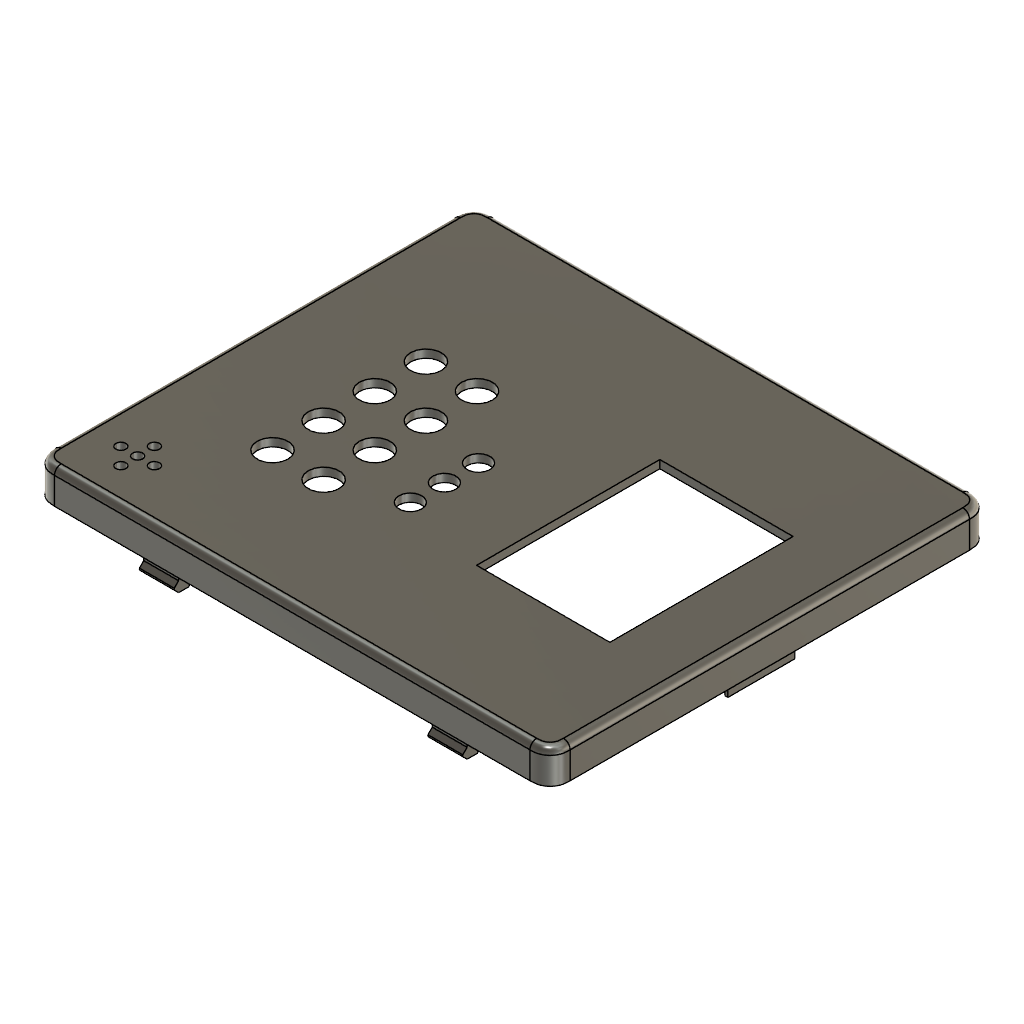
Крышка_пульта_клипсы_1.6_без_стоек (Autodesk Fusion 360 design; units mm, degrees)
part number: 2026-10-16-10-37-09-127
Autodesk Fusion 360 part; units mm, degrees
(part 1 of 3)
sketch "Sketch1" plane through (0, 0, 0) normal (0, 0, 1) x (1, 0, 0)
  line L0 (-25, 25) -> (41.8682, 25)
  line L1 (41.8682, 25) -> (41.8682, -32)
  line L2 (41.8682, -32) -> (-25, -32)
  line L3 (-25, -32) -> (-25, 25)
  dimension "d1" = 57
  constraint horizontal L0
  constraint vertical L1
  constraint horizontal L2
  constraint vertical L3
  measures "d1" distance of L0.start L2.end
extrude "Extrude1" add sketch "Sketch1" along normal blind 35 makes body 1
scale "Scale1" factor 1 about (-25, 25, 0) bodies 1
scale "Scale2" factor 1.105263 about (-25, 25, 35) bodies 1
scale "Scale3" factor 1.04 about (-25, -38, 35) bodies 1
fillet "Fillet1" radius 3 curvature continuous 4 edges at (-25, 27.52, 14.8842) (-25, -38, 14.8842) (51.8632, 27.52, 14.8842) (51.8632, -38, 14.8842) on bodies 1
ref_plane "WorkPlane1" through (13.4316, -5.24, 30) normal (0, 0, 1) x (1, 0, 0)
split "Split1" by plane through (13.4316, -5.24, 30) normal (0, 0, 1) bodies 1 makes body 2 at (1.6211, 5.68, 35)
move_body "Move1" bodies 2 to x (1, 0, 0) y (0, 1, 0) z (0, 0, 1) at (0, 0, 10)
extrude "Height clearance for 40 mm electronics" add 1 faces at (1.6211, 5.68, 30) along direction (0, 0, 1) blind 4 on bodies 1 bodies 1
shell "PETG housing walls 1.6 mm" thickness 1.2 removed faces 1 at (1.6211, 5.68, 34) on bodies 1
move_body "Assembled lid at housing rim" bodies 2 to x (1, 0, 0) y (0, 1, 0) z (0, 0, 1) at (0, 0, -6)
shell "PETG lid skin 1.2 mm" thickness 1.2 removed faces 1 at (1.6211, 5.68, 34) on bodies 2
ref_plane "WorkPlane2" through (0, 0, 30.2) normal (0, 0, 1) x (1, 0, 0)
sketch "PETG flexible clip -1 0" plane through (0, 0, 30.2) normal (0, 0, 1) x (1, 0, 0)
  line L0 (-10.6, -36.1) -> (-5.4, -36.1)
  line L1 (-5.4, -36.1) -> (-5.4, -35.3)
  line L2 (-5.4, -35.3) -> (-10.6, -35.3)
  line L3 (-10.6, -35.3) -> (-10.6, -36.1)
extrude "PETG flexible clip -1 0 (1)" add sketch "PETG flexible clip -1 0" along normal blind 7.8 bodies 2
ref_plane "WorkPlane3" through (-10.6, 0, 0) normal (1, 0, 0) x (0, 1, 0)
sketch "Latch ramp -1 0" plane through (-10.6, 0, 0) normal (1, 0, 0) x (0, 0, -1)
  line L0 (-30.2, -36.1) -> (-30.85, -36.75)
  line L1 (-30.85, -36.75) -> (-31.1, -36.75)
  line L2 (-31.1, -36.75) -> (-31.75, -36.1)
  line L3 (-31.75, -36.1) -> (-30.2, -36.1)
extrude "Latch ramp -1 0 (1)" add sketch "Latch ramp -1 0" along normal blind 5.2 bodies 2
ref_plane "WorkPlane4" through (0, -38.1, 0) normal (0, 1, 0) x (0, 0, 1)
sketch "Release slot -1 0" plane through (0, -38.1, 0) normal (0, 1, 0) x (1, 0, 0)
  line L0 (-11, -30.6) -> (-5, -30.6)
  line L1 (-5, -30.6) -> (-5, -31.4)
  line L2 (-5, -31.4) -> (-11, -31.4)
  line L3 (-11, -31.4) -> (-11, -30.6)
extrude "Release slot -1 0 (1)" cut sketch "Release slot -1 0" along normal blind 2 bodies 1
ref_plane "WorkPlane5" through (0, 0, 30.2) normal (0, 0, 1) x (1, 0, 0)
sketch "PETG flexible clip -1 1" plane through (0, 0, 30.2) normal (0, 0, 1) x (1, 0, 0)
  line L0 (32.4, -36.1) -> (37.6, -36.1)
  line L1 (37.6, -36.1) -> (37.6, -35.3)
  line L2 (37.6, -35.3) -> (32.4, -35.3)
  line L3 (32.4, -35.3) -> (32.4, -36.1)
extrude "PETG flexible clip -1 1 (1)" add sketch "PETG flexible clip -1 1" along normal blind 7.8 bodies 2
ref_plane "WorkPlane6" through (32.4, 0, 0) normal (1, 0, 0) x (0, 1, 0)
sketch "Latch ramp -1 1" plane through (32.4, 0, 0) normal (1, 0, 0) x (0, 0, -1)
  line L0 (-30.2, -36.1) -> (-30.85, -36.75)
  line L1 (-30.85, -36.75) -> (-31.1, -36.75)
  line L2 (-31.1, -36.75) -> (-31.75, -36.1)
  line L3 (-31.75, -36.1) -> (-30.2, -36.1)
extrude "Latch ramp -1 1 (1)" add sketch "Latch ramp -1 1" along normal blind 5.2 bodies 2
ref_plane "WorkPlane7" through (0, -38.1, 0) normal (0, 1, 0) x (0, 0, 1)
sketch "Release slot -1 1" plane through (0, -38.1, 0) normal (0, 1, 0) x (1, 0, 0)
  line L0 (32, -30.6) -> (38, -30.6)
  line L1 (38, -30.6) -> (38, -31.4)
  line L2 (38, -31.4) -> (32, -31.4)
  line L3 (32, -31.4) -> (32, -30.6)
extrude "Release slot -1 1 (1)" cut sketch "Release slot -1 1" along normal blind 2 bodies 1
ref_plane "WorkPlane8" through (0, 0, 30.2) normal (0, 0, 1) x (1, 0, 0)
sketch "PETG flexible clip 1 0" plane through (0, 0, 30.2) normal (0, 0, 1) x (1, 0, 0)
  line L0 (-10.6, 24.82) -> (-5.4, 24.82)
  line L1 (-5.4, 24.82) -> (-5.4, 25.62)
  line L2 (-5.4, 25.62) -> (-10.6, 25.62)
  line L3 (-10.6, 25.62) -> (-10.6, 24.82)
extrude "PETG flexible clip 1 0 (1)" add sketch "PETG flexible clip 1 0" along normal blind 7.8 bodies 2
ref_plane "WorkPlane9" through (-10.6, 0, 0) normal (1, 0, 0) x (0, 1, 0)
sketch "Latch ramp 1 0" plane through (-10.6, 0, 0) normal (1, 0, 0) x (0, 0, -1)
  line L0 (-30.2, 25.62) -> (-30.85, 26.27)
  line L1 (-30.85, 26.27) -> (-31.1, 26.27)
  line L2 (-31.1, 26.27) -> (-31.75, 25.62)
  line L3 (-31.75, 25.62) -> (-30.2, 25.62)
extrude "Latch ramp 1 0 (1)" add sketch "Latch ramp 1 0" along normal blind 5.2 bodies 2
ref_plane "WorkPlane10" through (0, 27.62, 0) normal (0, 1, 0) x (0, 0, 1)
sketch "Release slot 1 0" plane through (0, 27.62, 0) normal (0, 1, 0) x (1, 0, 0)
  line L0 (-11, -30.6) -> (-5, -30.6)
  line L1 (-5, -30.6) -> (-5, -31.4)
  line L2 (-5, -31.4) -> (-11, -31.4)
  line L3 (-11, -31.4) -> (-11, -30.6)
extrude "Release slot 1 0 (1)" cut sketch "Release slot 1 0" against normal blind 2 bodies 1
ref_plane "WorkPlane11" through (0, 0, 30.2) normal (0, 0, 1) x (1, 0, 0)
sketch "PETG flexible clip 1 1" plane through (0, 0, 30.2) normal (0, 0, 1) x (1, 0, 0)
  line L0 (32.4, 24.82) -> (37.6, 24.82)
  line L1 (37.6, 24.82) -> (37.6, 25.62)
  line L2 (37.6, 25.62) -> (32.4, 25.62)
  line L3 (32.4, 25.62) -> (32.4, 24.82)
ref_plane "WorkPlane12" through (32.4, 0, 0) normal (1, 0, 0) x (0, 1, 0)
sketch "Latch ramp 1 1" plane through (32.4, 0, 0) normal (1, 0, 0) x (0, 0, -1)
  line L0 (-30.2, 25.62) -> (-30.85, 26.27)
  line L1 (-30.85, 26.27) -> (-31.1, 26.27)
  line L2 (-31.1, 26.27) -> (-31.75, 25.62)
  line L3 (-31.75, 25.62) -> (-30.2, 25.62)
ref_plane "WorkPlane13" through (0, 27.62, 0) normal (0, 1, 0) x (0, 0, 1)
sketch "Release slot 1 1" plane through (0, 27.62, 0) normal (0, 1, 0) x (1, 0, 0)
  line L0 (32, -30.6) -> (38, -30.6)
  line L1 (38, -30.6) -> (38, -31.4)
  line L2 (38, -31.4) -> (32, -31.4)
  line L3 (32, -31.4) -> (32, -30.6)
ref_plane "WorkPlane14" through (0, 27.62, 0) normal (0, 1, 0) x (0, 0, 1)
sketch "Switch aperture 13 x 8.5 mm" plane through (0, 27.62, 0) normal (0, 1, 0) x (1, 0, 0)
  line L0 (23.5, -15.75) -> (36.5, -15.75)
  line L1 (36.5, -15.75) -> (36.5, -24.25)
  line L2 (36.5, -24.25) -> (23.5, -24.25)
  line L3 (23.5, -24.25) -> (23.5, -15.75)
ref_plane "WorkPlane15" through (0, 0, 31.5) normal (0, 0, 1) x (1, 0, 0)
sketch "Lid alignment guide" plane through (0, 0, 31.5) normal (0, 0, 1) x (1, 0, 0)
  line L0 (-23, -10) -> (-22.2, -10)
  line L1 (-22.2, -10) -> (-22.2, 0)
  line L2 (-22.2, 0) -> (-23, 0)
  line L3 (-23, 0) -> (-23, -10)
ref_plane "WorkPlane16" through (0, 0, 31.5) normal (0, 0, 1) x (1, 0, 0)
sketch "Lid alignment guide (1)" plane through (0, 0, 31.5) normal (0, 0, 1) x (1, 0, 0)
  line L0 (49.06, -10) -> (49.86, -10)
  line L1 (49.86, -10) -> (49.86, 0)
  line L2 (49.86, 0) -> (49.06, 0)
  line L3 (49.06, 0) -> (49.06, -10)
ref_plane "WorkPlane17" through (0, 0, 29.6) normal (0, 0, 1) x (1, 0, 0)
sketch "Local clip reinforcement" plane through (0, 0, 29.6) normal (0, 0, 1) x (1, 0, 0)
  line L0 (-11.5, -36.9) -> (-4.5, -36.9)
  line L1 (-4.5, -36.9) -> (-4.5, -36.4)
  line L2 (-4.5, -36.4) -> (-11.5, -36.4)
  line L3 (-11.5, -36.4) -> (-11.5, -36.9)
extrude "Local clip reinforcement (1)" add sketch "Local clip reinforcement" along normal blind 4.4 bodies 1
ref_plane "WorkPlane18" through (0, -38.1, 0) normal (0, 1, 0) x (0, 0, 1)
sketch "Clip clearance and release access" plane through (0, -38.1, 0) normal (0, 1, 0) x (1, 0, 0)
  line L0 (-11, -30.3) -> (-5, -30.3)
  line L1 (-5, -30.3) -> (-5, -31.65)
  line L2 (-5, -31.65) -> (-11, -31.65)
  line L3 (-11, -31.65) -> (-11, -30.3)
extrude "Clip clearance and release access (1)" cut sketch "Clip clearance and release access" along normal blind 2.1 bodies 1
ref_plane "WorkPlane19" through (0, 0, 29.6) normal (0, 0, 1) x (1, 0, 0)
sketch "Local clip reinforcement (1)" plane through (0, 0, 29.6) normal (0, 0, 1) x (1, 0, 0)
  line L0 (31.5, -36.9) -> (38.5, -36.9)
  line L1 (38.5, -36.9) -> (38.5, -36.4)
  line L2 (38.5, -36.4) -> (31.5, -36.4)
  line L3 (31.5, -36.4) -> (31.5, -36.9)
extrude "Local clip reinforcement (2)" add sketch "Local clip reinforcement (1)" along normal blind 4.4 bodies 1
ref_plane "WorkPlane20" through (0, -38.1, 0) normal (0, 1, 0) x (0, 0, 1)
sketch "Clip clearance and release access (1)" plane through (0, -38.1, 0) normal (0, 1, 0) x (1, 0, 0)
  line L0 (32, -30.3) -> (38, -30.3)
  line L1 (38, -30.3) -> (38, -31.65)
  line L2 (38, -31.65) -> (32, -31.65)
  line L3 (32, -31.65) -> (32, -30.3)
extrude "Clip clearance and release access (2)" cut sketch "Clip clearance and release access (1)" along normal blind 2.1 bodies 1
ref_plane "WorkPlane21" through (0, 0, 29.6) normal (0, 0, 1) x (1, 0, 0)
sketch "Local clip reinforcement (2)" plane through (0, 0, 29.6) normal (0, 0, 1) x (1, 0, 0)
  line L0 (-11.5, 25.92) -> (-4.5, 25.92)
  line L1 (-4.5, 25.92) -> (-4.5, 26.42)
  line L2 (-4.5, 26.42) -> (-11.5, 26.42)
  line L3 (-11.5, 26.42) -> (-11.5, 25.92)
extrude "Local clip reinforcement (3)" add sketch "Local clip reinforcement (2)" along normal blind 4.4 bodies 1
ref_plane "WorkPlane22" through (0, 27.62, 0) normal (0, 1, 0) x (0, 0, 1)
sketch "Clip clearance and release access (2)" plane through (0, 27.62, 0) normal (0, 1, 0) x (1, 0, 0)
  line L0 (-11, -30.3) -> (-5, -30.3)
  line L1 (-5, -30.3) -> (-5, -31.65)
  line L2 (-5, -31.65) -> (-11, -31.65)
  line L3 (-11, -31.65) -> (-11, -30.3)
extrude "Clip clearance and release access (3)" cut sketch "Clip clearance and release access (2)" against normal blind 2.1 bodies 1
ref_plane "WorkPlane23" through (0, 0, 29.6) normal (0, 0, 1) x (1, 0, 0)
sketch "Local clip reinforcement (3)" plane through (0, 0, 29.6) normal (0, 0, 1) x (1, 0, 0)
  line L0 (31.5, 25.92) -> (38.5, 25.92)
  line L1 (38.5, 25.92) -> (38.5, 26.42)
  line L2 (38.5, 26.42) -> (31.5, 26.42)
  line L3 (31.5, 26.42) -> (31.5, 25.92)
ref_plane "WorkPlane24" through (0, 27.62, 0) normal (0, 1, 0) x (0, 0, 1)
sketch "Clip clearance and release access (3)" plane through (0, 27.62, 0) normal (0, 1, 0) x (1, 0, 0)
  line L0 (32, -30.3) -> (38, -30.3)
  line L1 (38, -30.3) -> (38, -31.65)
  line L2 (38, -31.65) -> (32, -31.65)
  line L3 (32, -31.65) -> (32, -30.3)
ref_plane "WorkPlane25" through (0, 0, -4.08) normal (0, 0, 1) x (1, 0, 0)
sketch "PCB edge support PHOTO ESTIMATE" plane through (0, 0, -4.08) normal (0, 0, 1) x (1, 0, 0)
  line L0 (-20.5, -37) -> (-17.5, -37)
  line L1 (-17.5, -37) -> (-17.5, -34.4)
  line L2 (-17.5, -34.4) -> (-20.5, -34.4)
  line L3 (-20.5, -34.4) -> (-20.5, -37)
extrude "PCB edge support PHOTO ESTIMATE (1)" add sketch "PCB edge support PHOTO ESTIMATE" along normal blind 15.58 bodies 1
ref_plane "WorkPlane26" through (0, 0, -4.08) normal (0, 0, 1) x (1, 0, 0)
sketch "PCB edge support PHOTO ESTIMATE (1)" plane through (0, 0, -4.08) normal (0, 0, 1) x (1, 0, 0)
  line L0 (-20.5, 23.9) -> (-17.5, 23.9)
  line L1 (-17.5, 23.9) -> (-17.5, 26.52)
  line L2 (-17.5, 26.52) -> (-20.5, 26.52)
  line L3 (-20.5, 26.52) -> (-20.5, 23.9)
extrude "PCB edge support PHOTO ESTIMATE (2)" add sketch "PCB edge support PHOTO ESTIMATE (1)" along normal blind 15.58 bodies 1
ref_plane "WorkPlane27" through (0, 0, -4.08) normal (0, 0, 1) x (1, 0, 0)
sketch "PCB edge support PHOTO ESTIMATE (2)" plane through (0, 0, -4.08) normal (0, 0, 1) x (1, 0, 0)
  line L0 (44.5, -37) -> (47.5, -37)
  line L1 (47.5, -37) -> (47.5, -34.4)
  line L2 (47.5, -34.4) -> (44.5, -34.4)
  line L3 (44.5, -34.4) -> (44.5, -37)
extrude "PCB edge support PHOTO ESTIMATE (3)" add sketch "PCB edge support PHOTO ESTIMATE (2)" along normal blind 15.58 bodies 1
ref_plane "WorkPlane28" through (0, 0, -4.08) normal (0, 0, 1) x (1, 0, 0)
sketch "PCB edge support PHOTO ESTIMATE (3)" plane through (0, 0, -4.08) normal (0, 0, 1) x (1, 0, 0)
  line L0 (44.5, 23.9) -> (47.5, 23.9)
  line L1 (47.5, 23.9) -> (47.5, 26.52)
  line L2 (47.5, 26.52) -> (44.5, 26.52)
  line L3 (44.5, 26.52) -> (44.5, 23.9)
extrude "PCB edge support PHOTO ESTIMATE (4)" add sketch "PCB edge support PHOTO ESTIMATE (3)" along normal blind 15.58 bodies 1
ref_plane "WorkPlane29" through (51.9632, 0, 0) normal (1, 0, 0) x (0, 1, 0)
sketch "Antenna clearance PHOTO POSITION verify axis" plane through (51.9632, 0, 0) normal (1, 0, 0) x (0, 0, -1)
  circle A0 centre (-32.5, 17) radius 4
ref_plane "WorkPlane30" through (51.9632, 0, 0) normal (1, 0, 0) x (0, 1, 0)
sketch "USB C charge access PHOTO ESTIMATE" plane through (51.9632, 0, 0) normal (1, 0, 0) x (0, 0, -1)
  line L0 (-7, -21.5) -> (-7, -10.5)
  line L1 (-7, -10.5) -> (-12, -10.5)
  line L2 (-12, -10.5) -> (-12, -21.5)
  line L3 (-12, -21.5) -> (-7, -21.5)
ref_plane "WorkPlane31" through (-25.1, 0, 0) normal (1, 0, 0) x (0, 1, 0)
sketch "ESP USB service access PHOTO ESTIMATE" plane through (-25.1, 0, 0) normal (1, 0, 0) x (0, 0, -1)
  line L0 (-14.5, -21) -> (-14.5, -11)
  line L1 (-14.5, -11) -> (-19.5, -11)
  line L2 (-19.5, -11) -> (-19.5, -21)
  line L3 (-19.5, -21) -> (-14.5, -21)
ref_plane "WorkPlane32" through (0, 0, 39.1) normal (0, 0, 1) x (1, 0, 0)
sketch "OLED window 23 x 13 PHOTO ESTIMATE" plane through (0, 0, 39.1) normal (0, 0, 1) x (1, 0, 0)
  line L0 (26.5, -17) -> (39.5, -17)
  line L1 (39.5, -17) -> (39.5, 6)
  line L2 (39.5, 6) -> (26.5, 6)
  line L3 (26.5, 6) -> (26.5, -17)
ref_plane "WorkPlane33" through (0, 0, 39.1) normal (0, 0, 1) x (1, 0, 0)
sketch "Key aperture 1 pitch 7.62 PHOTO ESTIMATE" plane through (0, 0, 39.1) normal (0, 0, 1) x (1, 0, 0)
  circle A0 centre (-8, -17) radius 2.3
ref_plane "WorkPlane34" through (0, 0, 39.1) normal (0, 0, 1) x (1, 0, 0)
sketch "Key aperture 2 pitch 7.62 PHOTO ESTIMATE" plane through (0, 0, 39.1) normal (0, 0, 1) x (1, 0, 0)
  circle A0 centre (-8, -9.38) radius 2.3
ref_plane "WorkPlane35" through (0, 0, 39.1) normal (0, 0, 1) x (1, 0, 0)
sketch "Key aperture 3 pitch 7.62 PHOTO ESTIMATE" plane through (0, 0, 39.1) normal (0, 0, 1) x (1, 0, 0)
  circle A0 centre (-8, -1.76) radius 2.3
ref_plane "WorkPlane36" through (0, 0, 39.1) normal (0, 0, 1) x (1, 0, 0)
sketch "Key aperture 4 pitch 7.62 PHOTO ESTIMATE" plane through (0, 0, 39.1) normal (0, 0, 1) x (1, 0, 0)
  circle A0 centre (-8, 5.86) radius 2.3
ref_plane "WorkPlane37" through (0, 0, 39.1) normal (0, 0, 1) x (1, 0, 0)
sketch "Key aperture 5 pitch 7.62 PHOTO ESTIMATE" plane through (0, 0, 39.1) normal (0, 0, 1) x (1, 0, 0)
  circle A0 centre (-0.38, -17) radius 2.3
ref_plane "WorkPlane38" through (0, 0, 39.1) normal (0, 0, 1) x (1, 0, 0)
sketch "Key aperture 6 pitch 7.62 PHOTO ESTIMATE" plane through (0, 0, 39.1) normal (0, 0, 1) x (1, 0, 0)
  circle A0 centre (-0.38, -9.38) radius 2.3
ref_plane "WorkPlane39" through (0, 0, 39.1) normal (0, 0, 1) x (1, 0, 0)
sketch "Key aperture 7 pitch 7.62 PHOTO ESTIMATE" plane through (0, 0, 39.1) normal (0, 0, 1) x (1, 0, 0)
  circle A0 centre (-0.38, -1.76) radius 2.3
ref_plane "WorkPlane40" through (0, 0, 39.1) normal (0, 0, 1) x (1, 0, 0)
sketch "Key aperture 8 pitch 7.62 PHOTO ESTIMATE" plane through (0, 0, 39.1) normal (0, 0, 1) x (1, 0, 0)
  circle A0 centre (-0.38, 5.86) radius 2.3
ref_plane "WorkPlane41" through (0, 0, 39.1) normal (0, 0, 1) x (1, 0, 0)
sketch "LED aperture 1 PHOTO ESTIMATE" plane through (0, 0, 39.1) normal (0, 0, 1) x (1, 0, 0)
  circle A0 centre (9, -16) radius 2.7
ref_plane "WorkPlane42" through (0, 0, 39.1) normal (0, 0, 1) x (1, 0, 0)
sketch "LED aperture 2 PHOTO ESTIMATE" plane through (0, 0, 39.1) normal (0, 0, 1) x (1, 0, 0)
  circle A0 centre (9, -8.38) radius 2.7
ref_plane "WorkPlane43" through (0, 0, 39.1) normal (0, 0, 1) x (1, 0, 0)
sketch "LED aperture 3 PHOTO ESTIMATE" plane through (0, 0, 39.1) normal (0, 0, 1) x (1, 0, 0)
  circle A0 centre (9, -0.76) radius 2.7
ref_plane "WorkPlane44" through (0, 0, 39.1) normal (0, 0, 1) x (1, 0, 0)
sketch "Buzzer vent 0" plane through (0, 0, 39.1) normal (0, 0, 1) x (1, 0, 0)
  circle A0 centre (-17, 17) radius 0.75
ref_plane "WorkPlane45" through (0, 0, 39.1) normal (0, 0, 1) x (1, 0, 0)
sketch "Buzzer vent 1" plane through (0, 0, 39.1) normal (0, 0, 1) x (1, 0, 0)
  circle A0 centre (-14.5, 17) radius 0.75
ref_plane "WorkPlane46" through (0, 0, 39.1) normal (0, 0, 1) x (1, 0, 0)
sketch "Buzzer vent 2" plane through (0, 0, 39.1) normal (0, 0, 1) x (1, 0, 0)
  circle A0 centre (-19.5, 17) radius 0.75
ref_plane "WorkPlane47" through (0, 0, 39.1) normal (0, 0, 1) x (1, 0, 0)
sketch "Buzzer vent 3" plane through (0, 0, 39.1) normal (0, 0, 1) x (1, 0, 0)
  circle A0 centre (-17, 19.5) radius 0.75
ref_plane "WorkPlane48" through (0, 0, 39.1) normal (0, 0, 1) x (1, 0, 0)
sketch "Buzzer vent 4" plane through (0, 0, 39.1) normal (0, 0, 1) x (1, 0, 0)
  circle A0 centre (-17, 14.5) radius 0.75
ref_plane "WorkPlane49" through (0, 0, 33.1) normal (0, 0, 1) x (1, 0, 0)
sketch "Button 1 stem verify height" plane through (0, 0, 33.1) normal (0, 0, 1) x (1, 0, 0)
  circle A0 centre (-8, -17) radius 1.6
ref_plane "WorkPlane50" through (0, 0, 36.9) normal (0, 0, 1) x (1, 0, 0)
sketch "Button 1 retention flange" plane through (0, 0, 36.9) normal (0, 0, 1) x (1, 0, 0)
  circle A0 centre (-8, -17) radius 2.8
ref_plane "WorkPlane51" through (0, 0, 33.1) normal (0, 0, 1) x (1, 0, 0)
sketch "Button 2 stem verify height" plane through (0, 0, 33.1) normal (0, 0, 1) x (1, 0, 0)
  circle A0 centre (-8, -9.38) radius 1.6
ref_plane "WorkPlane52" through (0, 0, 36.9) normal (0, 0, 1) x (1, 0, 0)
sketch "Button 2 retention flange" plane through (0, 0, 36.9) normal (0, 0, 1) x (1, 0, 0)
  circle A0 centre (-8, -9.38) radius 2.8
ref_plane "WorkPlane53" through (0, 0, 33.1) normal (0, 0, 1) x (1, 0, 0)
sketch "Button 3 stem verify height" plane through (0, 0, 33.1) normal (0, 0, 1) x (1, 0, 0)
  circle A0 centre (-8, -1.76) radius 1.6
ref_plane "WorkPlane54" through (0, 0, 36.9) normal (0, 0, 1) x (1, 0, 0)
sketch "Button 3 retention flange" plane through (0, 0, 36.9) normal (0, 0, 1) x (1, 0, 0)
  circle A0 centre (-8, -1.76) radius 2.8
ref_plane "WorkPlane55" through (0, 0, 33.1) normal (0, 0, 1) x (1, 0, 0)
sketch "Button 4 stem verify height" plane through (0, 0, 33.1) normal (0, 0, 1) x (1, 0, 0)
  circle A0 centre (-8, 5.86) radius 1.6
ref_plane "WorkPlane56" through (0, 0, 36.9) normal (0, 0, 1) x (1, 0, 0)
sketch "Button 4 retention flange" plane through (0, 0, 36.9) normal (0, 0, 1) x (1, 0, 0)
  circle A0 centre (-8, 5.86) radius 2.8
ref_plane "WorkPlane57" through (0, 0, 33.1) normal (0, 0, 1) x (1, 0, 0)
sketch "Button 5 stem verify height" plane through (0, 0, 33.1) normal (0, 0, 1) x (1, 0, 0)
  circle A0 centre (-0.38, -17) radius 1.6
ref_plane "WorkPlane58" through (0, 0, 36.9) normal (0, 0, 1) x (1, 0, 0)
sketch "Button 5 retention flange" plane through (0, 0, 36.9) normal (0, 0, 1) x (1, 0, 0)
  circle A0 centre (-0.38, -17) radius 2.8
ref_plane "WorkPlane59" through (0, 0, 33.1) normal (0, 0, 1) x (1, 0, 0)
sketch "Button 6 stem verify height" plane through (0, 0, 33.1) normal (0, 0, 1) x (1, 0, 0)
  circle A0 centre (-0.38, -9.38) radius 1.6
ref_plane "WorkPlane60" through (0, 0, 36.9) normal (0, 0, 1) x (1, 0, 0)
sketch "Button 6 retention flange" plane through (0, 0, 36.9) normal (0, 0, 1) x (1, 0, 0)
  circle A0 centre (-0.38, -9.38) radius 2.8
ref_plane "WorkPlane61" through (0, 0, 33.1) normal (0, 0, 1) x (1, 0, 0)
sketch "Button 7 stem verify height" plane through (0, 0, 33.1) normal (0, 0, 1) x (1, 0, 0)
  circle A0 centre (-0.38, -1.76) radius 1.6
ref_plane "WorkPlane62" through (0, 0, 36.9) normal (0, 0, 1) x (1, 0, 0)
sketch "Button 7 retention flange" plane through (0, 0, 36.9) normal (0, 0, 1) x (1, 0, 0)
  circle A0 centre (-0.38, -1.76) radius 2.8
ref_plane "WorkPlane63" through (0, 0, 33.1) normal (0, 0, 1) x (1, 0, 0)
sketch "Button 8 stem verify height" plane through (0, 0, 33.1) normal (0, 0, 1) x (1, 0, 0)
  circle A0 centre (-0.38, 5.86) radius 1.6
ref_plane "WorkPlane64" through (0, 0, 36.9) normal (0, 0, 1) x (1, 0, 0)
sketch "Button 8 retention flange" plane through (0, 0, 36.9) normal (0, 0, 1) x (1, 0, 0)
  circle A0 centre (-0.38, 5.86) radius 2.8
ref_plane "WorkPlane65" through (0, 0, 11.5) normal (0, 0, 1) x (1, 0, 0)
sketch "Main PCB ESTIMATED 70x60x1.6" plane through (0, 0, 11.5) normal (0, 0, 1) x (1, 0, 0)
  line L0 (-21.5684, -35.24) -> (48.4316, -35.24)
  line L1 (48.4316, -35.24) -> (48.4316, 24.76)
  line L2 (48.4316, 24.76) -> (-21.5684, 24.76)
  line L3 (-21.5684, 24.76) -> (-21.5684, -35.24)
extrude "Main PCB ESTIMATED 70x60x1.6 (1)" add sketch "Main PCB ESTIMATED 70x60x1.6" along normal blind 1.6 separate body makes body 3
ref_plane "WorkPlane66" through (0, 0, -3.13) normal (0, 0, 1) x (1, 0, 0)
sketch "LiPo envelope ESTIMATED 34x44x10.5" plane through (0, 0, -3.13) normal (0, 0, 1) x (1, 0, 0)
  line L0 (-20, -27) -> (14, -27)
  line L1 (14, -27) -> (14, 17)
  line L2 (14, 17) -> (-20, 17)
  line L3 (-20, 17) -> (-20, -27)
extrude "LiPo envelope ESTIMATED 34x44x10.5 (1)" add sketch "LiPo envelope ESTIMATED 34x44x10.5" along normal blind 10.5 separate body makes body 4
ref_plane "WorkPlane67" through (0, 0, -2) normal (0, 0, 1) x (1, 0, 0)
sketch "DC DC module ESTIMATED 21x43x13" plane through (0, 0, -2) normal (0, 0, 1) x (1, 0, 0)
  line L0 (16, -26) -> (37, -26)
  line L1 (37, -26) -> (37, 17)
  line L2 (37, 17) -> (16, 17)
  line L3 (16, 17) -> (16, -26)
ref_plane "WorkPlane68" through (0, 0, 8.5) normal (0, 0, 1) x (1, 0, 0)
sketch "USB charging module ESTIMATED" plane through (0, 0, 8.5) normal (0, 0, 1) x (1, 0, 0)
  line L0 (30, -23) -> (49, -23)
  line L1 (49, -23) -> (49, -8)
  line L2 (49, -8) -> (30, -8)
  line L3 (30, -8) -> (30, -23)
ref_plane "WorkPlane69" through (0, 0, 13.1) normal (0, 0, 1) x (1, 0, 0)
sketch "ESP32 module ESTIMATED" plane through (0, 0, 13.1) normal (0, 0, 1) x (1, 0, 0)
  line L0 (-16, -25) -> (35, -25)
  line L1 (35, -25) -> (35, 0)
  line L2 (35, 0) -> (-16, 0)
  line L3 (-16, 0) -> (-16, -25)
ref_plane "WorkPlane70" through (0, 0, 17) normal (0, 0, 1) x (1, 0, 0)
sketch "Radio module ESTIMATED" plane through (0, 0, 17) normal (0, 0, 1) x (1, 0, 0)
  line L0 (16, 9) -> (49, 9)
  line L1 (49, 9) -> (49, 25)
  line L2 (49, 25) -> (16, 25)
  line L3 (16, 25) -> (16, 9)
ref_plane "WorkPlane71" through (0, 0, 31) normal (0, 0, 1) x (1, 0, 0)
sketch "OLED PCB ESTIMATED 26x29" plane through (0, 0, 31) normal (0, 0, 1) x (1, 0, 0)
  line L0 (20, -20) -> (46, -20)
  line L1 (46, -20) -> (46, 9)
  line L2 (46, 9) -> (20, 9)
  line L3 (20, 9) -> (20, -20)
ref_plane "WorkPlane72" through (0, 0, 32.6) normal (0, 0, 1) x (1, 0, 0)
sketch "OLED visible area ESTIMATED 13x23" plane through (0, 0, 32.6) normal (0, 0, 1) x (1, 0, 0)
  line L0 (26.5, -17) -> (39.5, -17)
  line L1 (39.5, -17) -> (39.5, 6)
  line L2 (39.5, 6) -> (26.5, 6)
  line L3 (26.5, 6) -> (26.5, -17)
ref_plane "WorkPlane73" through (0, 0, 28) normal (0, 0, 1) x (1, 0, 0)
sketch "Keypad PCB ESTIMATED 29x32" plane through (0, 0, 28) normal (0, 0, 1) x (1, 0, 0)
  line L0 (-14, -22) -> (15, -22)
  line L1 (15, -22) -> (15, 10)
  line L2 (15, 10) -> (-14, 10)
  line L3 (-14, 10) -> (-14, -22)
ref_plane "WorkPlane74" through (0, 0, 29.6) normal (0, 0, 1) x (1, 0, 0)
sketch "Tact switch 1 estimated" plane through (0, 0, 29.6) normal (0, 0, 1) x (1, 0, 0)
  circle A0 centre (-8, -17) radius 1.75
ref_plane "WorkPlane75" through (0, 0, 29.6) normal (0, 0, 1) x (1, 0, 0)
sketch "Tact switch 2 estimated" plane through (0, 0, 29.6) normal (0, 0, 1) x (1, 0, 0)
  circle A0 centre (-8, -9.38) radius 1.75
ref_plane "WorkPlane76" through (0, 0, 29.6) normal (0, 0, 1) x (1, 0, 0)
sketch "Tact switch 3 estimated" plane through (0, 0, 29.6) normal (0, 0, 1) x (1, 0, 0)
  circle A0 centre (-8, -1.76) radius 1.75
ref_plane "WorkPlane77" through (0, 0, 29.6) normal (0, 0, 1) x (1, 0, 0)
sketch "Tact switch 4 estimated" plane through (0, 0, 29.6) normal (0, 0, 1) x (1, 0, 0)
  circle A0 centre (-8, 5.86) radius 1.75
ref_plane "WorkPlane78" through (0, 0, 29.6) normal (0, 0, 1) x (1, 0, 0)
sketch "Tact switch 5 estimated" plane through (0, 0, 29.6) normal (0, 0, 1) x (1, 0, 0)
  circle A0 centre (-0.38, -17) radius 1.75
ref_plane "WorkPlane79" through (0, 0, 29.6) normal (0, 0, 1) x (1, 0, 0)
sketch "Tact switch 6 estimated" plane through (0, 0, 29.6) normal (0, 0, 1) x (1, 0, 0)
  circle A0 centre (-0.38, -9.38) radius 1.75
ref_plane "WorkPlane80" through (0, 0, 29.6) normal (0, 0, 1) x (1, 0, 0)
sketch "Tact switch 7 estimated" plane through (0, 0, 29.6) normal (0, 0, 1) x (1, 0, 0)
  circle A0 centre (-0.38, -1.76) radius 1.75
ref_plane "WorkPlane81" through (0, 0, 29.6) normal (0, 0, 1) x (1, 0, 0)
sketch "Tact switch 8 estimated" plane through (0, 0, 29.6) normal (0, 0, 1) x (1, 0, 0)
  circle A0 centre (-0.38, 5.86) radius 1.75
ref_plane "WorkPlane82" through (0, 0, 29.6) normal (0, 0, 1) x (1, 0, 0)
sketch "LED 1 estimated" plane through (0, 0, 29.6) normal (0, 0, 1) x (1, 0, 0)
  circle A0 centre (9, -16) radius 2.5
ref_plane "WorkPlane83" through (0, 0, 29.6) normal (0, 0, 1) x (1, 0, 0)
sketch "LED 2 estimated" plane through (0, 0, 29.6) normal (0, 0, 1) x (1, 0, 0)
  circle A0 centre (9, -8.38) radius 2.5
ref_plane "WorkPlane84" through (0, 0, 29.6) normal (0, 0, 1) x (1, 0, 0)
sketch "LED 3 estimated" plane through (0, 0, 29.6) normal (0, 0, 1) x (1, 0, 0)
  circle A0 centre (9, -0.76) radius 2.5
ref_plane "WorkPlane85" through (48.4316, 0, 0) normal (1, 0, 0) x (0, 1, 0)
sketch "SMA connector ESTIMATED verify diameter and axis" plane through (48.4316, 0, 0) normal (1, 0, 0) x (0, 0, -1)
  circle A0 centre (-32.5, 17) radius 3.175
extrude "SMA connector ESTIMATED verify diameter and axis (1)" add sketch "SMA connector ESTIMATED verify diameter and axis" along normal blind 9 separate body makes body 5
ref_plane "WorkPlane86" through (0, 0, 13.1) normal (0, 0, 1) x (1, 0, 0)
sketch "Buzzer ESTIMATED" plane through (0, 0, 13.1) normal (0, 0, 1) x (1, 0, 0)
  circle A0 centre (-17, 17) radius 4.5
ref_plane "WorkPlane87" through (0, 0, 15.75) normal (0, 0, 1) x (1, 0, 0)
sketch "Switch 13x8.5 USER DIMENSIONS depth estimated" plane through (0, 0, 15.75) normal (0, 0, 1) x (1, 0, 0)
  line L0 (23.5, 22) -> (36.5, 22)
  line L1 (36.5, 22) -> (36.5, 29)
  line L2 (36.5, 29) -> (23.5, 29)
  line L3 (23.5, 29) -> (23.5, 22)
extrude "Switch 13x8.5 USER DIMENSIONS depth estimated (1)" add sketch "Switch 13x8.5 USER DIMENSIONS depth estimated" along normal blind 8.5 separate body makes body 6
ref_plane "WorkPlane88" through (0, 0, 27.75) normal (0, 0, 1) x (1, 0, 0)
sketch "Keypad spring edge finger DRAFT" plane through (0, 0, 27.75) normal (0, 0, 1) x (1, 0, 0)
  line L0 (-13, -23.1) -> (-9, -23.1)
  line L1 (-9, -23.1) -> (-9, -22.3)
  line L2 (-9, -22.3) -> (-13, -22.3)
  line L3 (-13, -22.3) -> (-13, -23.1)
ref_plane "WorkPlane89" through (-13, 0, 0) normal (1, 0, 0) x (0, 1, 0)
sketch "Keypad retention lead-in DRAFT" plane through (-13, 0, 0) normal (1, 0, 0) x (0, 0, -1)
  line L0 (-27.75, -22.3) -> (-27.75, -21.3)
  line L1 (-27.75, -21.3) -> (-28, -21.3)
  line L2 (-28, -21.3) -> (-29, -22.3)
  line L3 (-29, -22.3) -> (-27.75, -22.3)
ref_plane "WorkPlane90" through (0, 0, 29.7) normal (0, 0, 1) x (1, 0, 0)
sketch "Keypad top spacer DRAFT" plane through (0, 0, 29.7) normal (0, 0, 1) x (1, 0, 0)
  line L0 (-12, -22) -> (-10, -22)
  line L1 (-10, -22) -> (-10, -21)
  line L2 (-10, -21) -> (-12, -21)
  line L3 (-12, -21) -> (-12, -22)
ref_plane "WorkPlane91" through (0, 0, 27.75) normal (0, 0, 1) x (1, 0, 0)
sketch "Keypad spring edge finger DRAFT (1)" plane through (0, 0, 27.75) normal (0, 0, 1) x (1, 0, 0)
  line L0 (-13, 10.3) -> (-9, 10.3)
  line L1 (-9, 10.3) -> (-9, 11.1)
  line L2 (-9, 11.1) -> (-13, 11.1)
  line L3 (-13, 11.1) -> (-13, 10.3)
ref_plane "WorkPlane92" through (-13, 0, 0) normal (1, 0, 0) x (0, 1, 0)
sketch "Keypad retention lead-in DRAFT (1)" plane through (-13, 0, 0) normal (1, 0, 0) x (0, 0, -1)
  line L0 (-27.75, 10.3) -> (-27.75, 9.3)
  line L1 (-27.75, 9.3) -> (-28, 9.3)
  line L2 (-28, 9.3) -> (-29, 10.3)
  line L3 (-29, 10.3) -> (-27.75, 10.3)
ref_plane "WorkPlane93" through (0, 0, 29.7) normal (0, 0, 1) x (1, 0, 0)
sketch "Keypad top spacer DRAFT (1)" plane through (0, 0, 29.7) normal (0, 0, 1) x (1, 0, 0)
  line L0 (-12, 9) -> (-10, 9)
  line L1 (-10, 9) -> (-10, 10)
  line L2 (-10, 10) -> (-12, 10)
  line L3 (-12, 10) -> (-12, 9)
ref_plane "WorkPlane94" through (0, 0, 27.75) normal (0, 0, 1) x (1, 0, 0)
sketch "Keypad spring edge finger DRAFT (2)" plane through (0, 0, 27.75) normal (0, 0, 1) x (1, 0, 0)
  line L0 (10, -23.1) -> (14, -23.1)
  line L1 (14, -23.1) -> (14, -22.3)
  line L2 (14, -22.3) -> (10, -22.3)
  line L3 (10, -22.3) -> (10, -23.1)
ref_plane "WorkPlane95" through (10, 0, 0) normal (1, 0, 0) x (0, 1, 0)
sketch "Keypad retention lead-in DRAFT (2)" plane through (10, 0, 0) normal (1, 0, 0) x (0, 0, -1)
  line L0 (-27.75, -22.3) -> (-27.75, -21.3)
  line L1 (-27.75, -21.3) -> (-28, -21.3)
  line L2 (-28, -21.3) -> (-29, -22.3)
  line L3 (-29, -22.3) -> (-27.75, -22.3)
ref_plane "WorkPlane96" through (0, 0, 29.7) normal (0, 0, 1) x (1, 0, 0)
sketch "Keypad top spacer DRAFT (2)" plane through (0, 0, 29.7) normal (0, 0, 1) x (1, 0, 0)
  line L0 (11, -22) -> (13, -22)
  line L1 (13, -22) -> (13, -21)
  line L2 (13, -21) -> (11, -21)
  line L3 (11, -21) -> (11, -22)
ref_plane "WorkPlane97" through (0, 0, 27.75) normal (0, 0, 1) x (1, 0, 0)
sketch "Keypad spring edge finger DRAFT (3)" plane through (0, 0, 27.75) normal (0, 0, 1) x (1, 0, 0)
  line L0 (10, 10.3) -> (14, 10.3)
  line L1 (14, 10.3) -> (14, 11.1)
  line L2 (14, 11.1) -> (10, 11.1)
  line L3 (10, 11.1) -> (10, 10.3)
ref_plane "WorkPlane98" through (10, 0, 0) normal (1, 0, 0) x (0, 1, 0)
sketch "Keypad retention lead-in DRAFT (3)" plane through (10, 0, 0) normal (1, 0, 0) x (0, 0, -1)
  line L0 (-27.75, 10.3) -> (-27.75, 9.3)
  line L1 (-27.75, 9.3) -> (-28, 9.3)
  line L2 (-28, 9.3) -> (-29, 10.3)
  line L3 (-29, 10.3) -> (-27.75, 10.3)
ref_plane "WorkPlane99" through (0, 0, 29.7) normal (0, 0, 1) x (1, 0, 0)
sketch "Keypad top spacer DRAFT (3)" plane through (0, 0, 29.7) normal (0, 0, 1) x (1, 0, 0)
  line L0 (11, 9) -> (13, 9)
  line L1 (13, 9) -> (13, 10)
  line L2 (13, 10) -> (11, 10)
  line L3 (11, 10) -> (11, 9)
ref_plane "WorkPlane100" through (0, 0, 30.75) normal (0, 0, 1) x (1, 0, 0)
sketch "OLED spring edge finger DRAFT" plane through (0, 0, 30.75) normal (0, 0, 1) x (1, 0, 0)
  line L0 (20, -21.1) -> (24, -21.1)
  line L1 (24, -21.1) -> (24, -20.3)
  line L2 (24, -20.3) -> (20, -20.3)
  line L3 (20, -20.3) -> (20, -21.1)
ref_plane "WorkPlane101" through (20, 0, 0) normal (1, 0, 0) x (0, 1, 0)
sketch "OLED retention lead-in DRAFT" plane through (20, 0, 0) normal (1, 0, 0) x (0, 0, -1)
  line L0 (-30.75, -20.3) -> (-30.75, -19.3)
  line L1 (-30.75, -19.3) -> (-31, -19.3)
  line L2 (-31, -19.3) -> (-32, -20.3)
  line L3 (-32, -20.3) -> (-30.75, -20.3)
ref_plane "WorkPlane102" through (0, 0, 32.7) normal (0, 0, 1) x (1, 0, 0)
sketch "OLED top spacer DRAFT" plane through (0, 0, 32.7) normal (0, 0, 1) x (1, 0, 0)
  line L0 (21, -20) -> (23, -20)
  line L1 (23, -20) -> (23, -19)
  line L2 (23, -19) -> (21, -19)
  line L3 (21, -19) -> (21, -20)
ref_plane "WorkPlane103" through (0, 0, 30.75) normal (0, 0, 1) x (1, 0, 0)
sketch "OLED spring edge finger DRAFT (1)" plane through (0, 0, 30.75) normal (0, 0, 1) x (1, 0, 0)
  line L0 (20, 9.3) -> (24, 9.3)
  line L1 (24, 9.3) -> (24, 10.1)
  line L2 (24, 10.1) -> (20, 10.1)
  line L3 (20, 10.1) -> (20, 9.3)
ref_plane "WorkPlane104" through (20, 0, 0) normal (1, 0, 0) x (0, 1, 0)
sketch "OLED retention lead-in DRAFT (1)" plane through (20, 0, 0) normal (1, 0, 0) x (0, 0, -1)
  line L0 (-30.75, 9.3) -> (-30.75, 8.3)
  line L1 (-30.75, 8.3) -> (-31, 8.3)
  line L2 (-31, 8.3) -> (-32, 9.3)
  line L3 (-32, 9.3) -> (-30.75, 9.3)
ref_plane "WorkPlane105" through (0, 0, 32.7) normal (0, 0, 1) x (1, 0, 0)
sketch "OLED top spacer DRAFT (1)" plane through (0, 0, 32.7) normal (0, 0, 1) x (1, 0, 0)
  line L0 (21, 8) -> (23, 8)
  line L1 (23, 8) -> (23, 9)
  line L2 (23, 9) -> (21, 9)
  line L3 (21, 9) -> (21, 8)
ref_plane "WorkPlane106" through (0, 0, 30.75) normal (0, 0, 1) x (1, 0, 0)
sketch "OLED spring edge finger DRAFT (2)" plane through (0, 0, 30.75) normal (0, 0, 1) x (1, 0, 0)
  line L0 (42, -21.1) -> (46, -21.1)
  line L1 (46, -21.1) -> (46, -20.3)
  line L2 (46, -20.3) -> (42, -20.3)
  line L3 (42, -20.3) -> (42, -21.1)
ref_plane "WorkPlane107" through (42, 0, 0) normal (1, 0, 0) x (0, 1, 0)
sketch "OLED retention lead-in DRAFT (2)" plane through (42, 0, 0) normal (1, 0, 0) x (0, 0, -1)
  line L0 (-30.75, -20.3) -> (-30.75, -19.3)
  line L1 (-30.75, -19.3) -> (-31, -19.3)
  line L2 (-31, -19.3) -> (-32, -20.3)
  line L3 (-32, -20.3) -> (-30.75, -20.3)
ref_plane "WorkPlane108" through (0, 0, 32.7) normal (0, 0, 1) x (1, 0, 0)
sketch "OLED top spacer DRAFT (2)" plane through (0, 0, 32.7) normal (0, 0, 1) x (1, 0, 0)
  line L0 (43, -20) -> (45, -20)
  line L1 (45, -20) -> (45, -19)
  line L2 (45, -19) -> (43, -19)
  line L3 (43, -19) -> (43, -20)
ref_plane "WorkPlane109" through (0, 0, 30.75) normal (0, 0, 1) x (1, 0, 0)
sketch "OLED spring edge finger DRAFT (3)" plane through (0, 0, 30.75) normal (0, 0, 1) x (1, 0, 0)
  line L0 (42, 9.3) -> (46, 9.3)
  line L1 (46, 9.3) -> (46, 10.1)
  line L2 (46, 10.1) -> (42, 10.1)
  line L3 (42, 10.1) -> (42, 9.3)
ref_plane "WorkPlane110" through (42, 0, 0) normal (1, 0, 0) x (0, 1, 0)
sketch "OLED retention lead-in DRAFT (3)" plane through (42, 0, 0) normal (1, 0, 0) x (0, 0, -1)
  line L0 (-30.75, 9.3) -> (-30.75, 8.3)
  line L1 (-30.75, 8.3) -> (-31, 8.3)
  line L2 (-31, 8.3) -> (-32, 9.3)
  line L3 (-32, 9.3) -> (-30.75, 9.3)
ref_plane "WorkPlane111" through (0, 0, 32.7) normal (0, 0, 1) x (1, 0, 0)
sketch "OLED top spacer DRAFT (3)" plane through (0, 0, 32.7) normal (0, 0, 1) x (1, 0, 0)
  line L0 (43, 8) -> (45, 8)
  line L1 (45, 8) -> (45, 9)
  line L2 (45, 9) -> (43, 9)
  line L3 (43, 9) -> (43, 8)
ref_plane "WorkPlane112" through (0, 0, 13.3) normal (0, 0, 1) x (1, 0, 0)
sketch "Main PCB edge retainer DRAFT" plane through (0, 0, 13.3) normal (0, 0, 1) x (1, 0, 0)
  line L0 (-20, -36.9) -> (-18, -36.9)
  line L1 (-18, -36.9) -> (-18, -34.9)
  line L2 (-18, -34.9) -> (-20, -34.9)
  line L3 (-20, -34.9) -> (-20, -36.9)
ref_plane "WorkPlane113" through (0, 0, 13.3) normal (0, 0, 1) x (1, 0, 0)
sketch "Main PCB edge retainer DRAFT (1)" plane through (0, 0, 13.3) normal (0, 0, 1) x (1, 0, 0)
  line L0 (-20, 24.4) -> (-18, 24.4)
  line L1 (-18, 24.4) -> (-18, 26.42)
  line L2 (-18, 26.42) -> (-20, 26.42)
  line L3 (-20, 26.42) -> (-20, 24.4)
ref_plane "WorkPlane114" through (0, 0, 13.3) normal (0, 0, 1) x (1, 0, 0)
sketch "Main PCB edge retainer DRAFT (2)" plane through (0, 0, 13.3) normal (0, 0, 1) x (1, 0, 0)
  line L0 (45, -36.9) -> (47, -36.9)
  line L1 (47, -36.9) -> (47, -34.9)
  line L2 (47, -34.9) -> (45, -34.9)
  line L3 (45, -34.9) -> (45, -36.9)
ref_plane "WorkPlane115" through (0, 0, 13.3) normal (0, 0, 1) x (1, 0, 0)
sketch "Main PCB edge retainer DRAFT (3)" plane through (0, 0, 13.3) normal (0, 0, 1) x (1, 0, 0)
  line L0 (45, 24.4) -> (47, 24.4)
  line L1 (47, 24.4) -> (47, 26.42)
  line L2 (47, 26.42) -> (45, 26.42)
  line L3 (45, 26.42) -> (45, 24.4)
ref_plane "WorkPlane116" through (0, 0, -4.08) normal (0, 0, 1) x (1, 0, 0)
sketch "Battery side fence DRAFT" plane through (0, 0, -4.08) normal (0, 0, 1) x (1, 0, 0)
  line L0 (-21.1, -23) -> (-20.5, -23)
  line L1 (-20.5, -23) -> (-20.5, 13)
  line L2 (-20.5, 13) -> (-21.1, 13)
  line L3 (-21.1, 13) -> (-21.1, -23)
extrude "Battery side fence DRAFT (1)" add sketch "Battery side fence DRAFT" along normal blind 3.08 bodies 1
ref_plane "WorkPlane117" through (0, 0, -4.08) normal (0, 0, 1) x (1, 0, 0)
sketch "Battery side fence DRAFT (1)" plane through (0, 0, -4.08) normal (0, 0, 1) x (1, 0, 0)
  line L0 (14.5, -23) -> (15.1, -23)
  line L1 (15.1, -23) -> (15.1, 13)
  line L2 (15.1, 13) -> (14.5, 13)
  line L3 (14.5, 13) -> (14.5, -23)
extrude "Battery side fence DRAFT (2)" add sketch "Battery side fence DRAFT (1)" along normal blind 3.08 bodies 1
ref_plane "WorkPlane118" through (0, 0, -4.08) normal (0, 0, 1) x (1, 0, 0)
sketch "Battery end fence DRAFT" plane through (0, 0, -4.08) normal (0, 0, 1) x (1, 0, 0)
  line L0 (-16, -28.1) -> (10, -28.1)
  line L1 (10, -28.1) -> (10, -27.5)
  line L2 (10, -27.5) -> (-16, -27.5)
  line L3 (-16, -27.5) -> (-16, -28.1)
ref_plane "WorkPlane119" through (0, 0, -4.08) normal (0, 0, 1) x (1, 0, 0)
sketch "Battery end fence DRAFT (1)" plane through (0, 0, -4.08) normal (0, 0, 1) x (1, 0, 0)
  line L0 (-16, 17.5) -> (10, 17.5)
  line L1 (10, 17.5) -> (10, 18.1)
  line L2 (10, 18.1) -> (-16, 18.1)
  line L3 (-16, 18.1) -> (-16, 17.5)
ref_plane "WorkPlane120" through (0, 0, -4.08) normal (0, 0, 1) x (1, 0, 0)
sketch "DC DC tape mounting pad DRAFT" plane through (0, 0, -4.08) normal (0, 0, 1) x (1, 0, 0)
  line L0 (16, -26) -> (18, -26)
  line L1 (18, -26) -> (18, -24)
  line L2 (18, -24) -> (16, -24)
  line L3 (16, -24) -> (16, -26)
ref_plane "WorkPlane121" through (0, 0, -4.08) normal (0, 0, 1) x (1, 0, 0)
sketch "DC DC tape mounting pad DRAFT (1)" plane through (0, 0, -4.08) normal (0, 0, 1) x (1, 0, 0)
  line L0 (16, 15) -> (18, 15)
  line L1 (18, 15) -> (18, 17)
  line L2 (18, 17) -> (16, 17)
  line L3 (16, 17) -> (16, 15)
ref_plane "WorkPlane122" through (0, 0, -4.08) normal (0, 0, 1) x (1, 0, 0)
sketch "DC DC tape mounting pad DRAFT (2)" plane through (0, 0, -4.08) normal (0, 0, 1) x (1, 0, 0)
  line L0 (35, -26) -> (37, -26)
  line L1 (37, -26) -> (37, -24)
  line L2 (37, -24) -> (35, -24)
  line L3 (35, -24) -> (35, -26)
ref_plane "WorkPlane123" through (0, 0, -4.08) normal (0, 0, 1) x (1, 0, 0)
sketch "DC DC tape mounting pad DRAFT (3)" plane through (0, 0, -4.08) normal (0, 0, 1) x (1, 0, 0)
  line L0 (35, 15) -> (37, 15)
  line L1 (37, 15) -> (37, 17)
  line L2 (37, 17) -> (35, 17)
  line L3 (35, 17) -> (35, 15)
ref_plane "WorkPlane124" through (0, 0, 39.1) normal (0, 0, 1) x (1, 0, 0)
sketch "OLED window 30 x 16 refined PHOTO ESTIMATE" plane through (0, 0, 39.1) normal (0, 0, 1) x (1, 0, 0)
  line L0 (25, -20.5) -> (41, -20.5)
  line L1 (41, -20.5) -> (41, 9.5)
  line L2 (41, 9.5) -> (25, 9.5)
  line L3 (25, 9.5) -> (25, -20.5)
ref_plane "WorkPlane125" through (0, 0, 30.75) normal (0, 0, 1) x (1, 0, 0)
sketch "OLED flexible holder PHOTO ESTIMATE" plane through (0, 0, 30.75) normal (0, 0, 1) x (1, 0, 0)
  line L0 (16.5, -24.35) -> (20.5, -24.35)
  line L1 (20.5, -24.35) -> (20.5, -23.55)
  line L2 (20.5, -23.55) -> (16.5, -23.55)
  line L3 (16.5, -23.55) -> (16.5, -24.35)
ref_plane "WorkPlane126" through (16.5, 0, 0) normal (1, 0, 0) x (0, 1, 0)
sketch "OLED retaining lip PHOTO ESTIMATE" plane through (16.5, 0, 0) normal (1, 0, 0) x (0, 0, -1)
  line L0 (-30.75, -23.55) -> (-30.75, -22.55)
  line L1 (-30.75, -22.55) -> (-31, -22.55)
  line L2 (-31, -22.55) -> (-32, -23.55)
  line L3 (-32, -23.55) -> (-30.75, -23.55)
ref_plane "WorkPlane127" through (0, 0, 32.7) normal (0, 0, 1) x (1, 0, 0)
sketch "OLED upper spacer PHOTO ESTIMATE" plane through (0, 0, 32.7) normal (0, 0, 1) x (1, 0, 0)
  line L0 (17.5, -23.25) -> (19.5, -23.25)
  line L1 (19.5, -23.25) -> (19.5, -22.25)
  line L2 (19.5, -22.25) -> (17.5, -22.25)
  line L3 (17.5, -22.25) -> (17.5, -23.25)
ref_plane "WorkPlane128" through (0, 0, 30.75) normal (0, 0, 1) x (1, 0, 0)
sketch "OLED flexible holder PHOTO ESTIMATE (1)" plane through (0, 0, 30.75) normal (0, 0, 1) x (1, 0, 0)
  line L0 (16.5, 12.55) -> (20.5, 12.55)
  line L1 (20.5, 12.55) -> (20.5, 13.35)
  line L2 (20.5, 13.35) -> (16.5, 13.35)
  line L3 (16.5, 13.35) -> (16.5, 12.55)
ref_plane "WorkPlane129" through (16.5, 0, 0) normal (1, 0, 0) x (0, 1, 0)
sketch "OLED retaining lip PHOTO ESTIMATE (1)" plane through (16.5, 0, 0) normal (1, 0, 0) x (0, 0, -1)
  line L0 (-30.75, 12.55) -> (-30.75, 11.55)
  line L1 (-30.75, 11.55) -> (-31, 11.55)
  line L2 (-31, 11.55) -> (-32, 12.55)
  line L3 (-32, 12.55) -> (-30.75, 12.55)
ref_plane "WorkPlane130" through (0, 0, 32.7) normal (0, 0, 1) x (1, 0, 0)
sketch "OLED upper spacer PHOTO ESTIMATE (1)" plane through (0, 0, 32.7) normal (0, 0, 1) x (1, 0, 0)
  line L0 (17.5, 11.25) -> (19.5, 11.25)
  line L1 (19.5, 11.25) -> (19.5, 12.25)
  line L2 (19.5, 12.25) -> (17.5, 12.25)
  line L3 (17.5, 12.25) -> (17.5, 11.25)
ref_plane "WorkPlane131" through (0, 0, 30.75) normal (0, 0, 1) x (1, 0, 0)
sketch "OLED flexible holder PHOTO ESTIMATE (2)" plane through (0, 0, 30.75) normal (0, 0, 1) x (1, 0, 0)
  line L0 (45.5, -24.35) -> (49.5, -24.35)
  line L1 (49.5, -24.35) -> (49.5, -23.55)
  line L2 (49.5, -23.55) -> (45.5, -23.55)
  line L3 (45.5, -23.55) -> (45.5, -24.35)
ref_plane "WorkPlane132" through (45.5, 0, 0) normal (1, 0, 0) x (0, 1, 0)
sketch "OLED retaining lip PHOTO ESTIMATE (2)" plane through (45.5, 0, 0) normal (1, 0, 0) x (0, 0, -1)
  line L0 (-30.75, -23.55) -> (-30.75, -22.55)
  line L1 (-30.75, -22.55) -> (-31, -22.55)
  line L2 (-31, -22.55) -> (-32, -23.55)
  line L3 (-32, -23.55) -> (-30.75, -23.55)
ref_plane "WorkPlane133" through (0, 0, 32.7) normal (0, 0, 1) x (1, 0, 0)
sketch "OLED upper spacer PHOTO ESTIMATE (2)" plane through (0, 0, 32.7) normal (0, 0, 1) x (1, 0, 0)
  line L0 (46.5, -23.25) -> (48.5, -23.25)
  line L1 (48.5, -23.25) -> (48.5, -22.25)
  line L2 (48.5, -22.25) -> (46.5, -22.25)
  line L3 (46.5, -22.25) -> (46.5, -23.25)
ref_plane "WorkPlane134" through (0, 0, 30.75) normal (0, 0, 1) x (1, 0, 0)
sketch "OLED flexible holder PHOTO ESTIMATE (3)" plane through (0, 0, 30.75) normal (0, 0, 1) x (1, 0, 0)
  line L0 (45.5, 12.55) -> (49.5, 12.55)
  line L1 (49.5, 12.55) -> (49.5, 13.35)
  line L2 (49.5, 13.35) -> (45.5, 13.35)
  line L3 (45.5, 13.35) -> (45.5, 12.55)
ref_plane "WorkPlane135" through (45.5, 0, 0) normal (1, 0, 0) x (0, 1, 0)
sketch "OLED retaining lip PHOTO ESTIMATE (3)" plane through (45.5, 0, 0) normal (1, 0, 0) x (0, 0, -1)
  line L0 (-30.75, 12.55) -> (-30.75, 11.55)
  line L1 (-30.75, 11.55) -> (-31, 11.55)
  line L2 (-31, 11.55) -> (-32, 12.55)
  line L3 (-32, 12.55) -> (-30.75, 12.55)
ref_plane "WorkPlane136" through (0, 0, 32.7) normal (0, 0, 1) x (1, 0, 0)
sketch "OLED upper spacer PHOTO ESTIMATE (3)" plane through (0, 0, 32.7) normal (0, 0, 1) x (1, 0, 0)
  line L0 (46.5, 11.25) -> (48.5, 11.25)
  line L1 (48.5, 11.25) -> (48.5, 12.25)
  line L2 (48.5, 12.25) -> (46.5, 12.25)
  line L3 (46.5, 12.25) -> (46.5, 11.25)
ref_plane "WorkPlane137" through (51.9632, 0, 0) normal (1, 0, 0) x (0, 1, 0)
sketch "Antenna matching lid relief PHOTO ESTIMATE" plane through (51.9632, 0, 0) normal (1, 0, 0) x (0, 0, -1)
  circle A0 centre (-32.5, 17) radius 4
ref_plane "WorkPlane138" through (0, 27.62, 0) normal (0, 1, 0) x (0, 0, 1)
sketch "Switch PETG clearance 13.4 x 8.9" plane through (0, 27.62, 0) normal (0, 1, 0) x (1, 0, 0)
  line L0 (23.3, -15.55) -> (36.7, -15.55)
  line L1 (36.7, -15.55) -> (36.7, -24.45)
  line L2 (36.7, -24.45) -> (23.3, -24.45)
  line L3 (23.3, -24.45) -> (23.3, -15.55)
ref_plane "WorkPlane139" through (0, 0, 31) normal (0, 0, 1) x (1, 0, 0)
sketch "REF_DO_NOT_PRINT OLED PCB estimated 33.5x35.5" plane through (0, 0, 31) normal (0, 0, 1) x (1, 0, 0)
  line L0 (16.25, -23.25) -> (49.75, -23.25)
  line L1 (49.75, -23.25) -> (49.75, 12.25)
  line L2 (49.75, 12.25) -> (16.25, 12.25)
  line L3 (16.25, 12.25) -> (16.25, -23.25)
ref_plane "WorkPlane140" through (0, 0, 32.6) normal (0, 0, 1) x (1, 0, 0)
sketch "REF_DO_NOT_PRINT OLED window estimate 16x30" plane through (0, 0, 32.6) normal (0, 0, 1) x (1, 0, 0)
  line L0 (25, -20.5) -> (41, -20.5)
  line L1 (41, -20.5) -> (41, 9.5)
  line L2 (41, 9.5) -> (25, 9.5)
  line L3 (25, 9.5) -> (25, -20.5)
ref_plane "WorkPlane141" through (0, 0, 27.3) normal (0, 0, 1) x (1, 0, 0)
sketch "REF_DO_NOT_PRINT Radio PCB estimated" plane through (0, 0, 27.3) normal (0, 0, 1) x (1, 0, 0)
  line L0 (16, 9) -> (49, 9)
  line L1 (49, 9) -> (49, 25)
  line L2 (49, 25) -> (16, 25)
  line L3 (16, 25) -> (16, 9)
ref_plane "WorkPlane142" through (0, 0, 36.1) normal (0, 0, 1) x (1, 0, 0)
sketch "Button printable flange taper" plane through (0, 0, 36.1) normal (0, 0, 1) x (1, 0, 0)
  circle A0 centre (-8, -17) radius 1.6
ref_plane "WorkPlane143" through (0, 0, 36.1) normal (0, 0, 1) x (1, 0, 0)
sketch "Button printable flange taper (1)" plane through (0, 0, 36.1) normal (0, 0, 1) x (1, 0, 0)
  circle A0 centre (-8, -9.38) radius 1.6
ref_plane "WorkPlane144" through (0, 0, 36.1) normal (0, 0, 1) x (1, 0, 0)
sketch "Button printable flange taper (2)" plane through (0, 0, 36.1) normal (0, 0, 1) x (1, 0, 0)
  circle A0 centre (-8, -1.76) radius 1.6
ref_plane "WorkPlane145" through (0, 0, 36.1) normal (0, 0, 1) x (1, 0, 0)
sketch "Button printable flange taper (3)" plane through (0, 0, 36.1) normal (0, 0, 1) x (1, 0, 0)
  circle A0 centre (-8, 5.86) radius 1.6
ref_plane "WorkPlane146" through (0, 0, 36.1) normal (0, 0, 1) x (1, 0, 0)
sketch "Button printable flange taper (4)" plane through (0, 0, 36.1) normal (0, 0, 1) x (1, 0, 0)
  circle A0 centre (-0.38, -17) radius 1.6
ref_plane "WorkPlane147" through (0, 0, 36.1) normal (0, 0, 1) x (1, 0, 0)
sketch "Button printable flange taper (5)" plane through (0, 0, 36.1) normal (0, 0, 1) x (1, 0, 0)
  circle A0 centre (-0.38, -9.38) radius 1.6
ref_plane "WorkPlane148" through (0, 0, 36.1) normal (0, 0, 1) x (1, 0, 0)
sketch "Button printable flange taper (6)" plane through (0, 0, 36.1) normal (0, 0, 1) x (1, 0, 0)
  circle A0 centre (-0.38, -1.76) radius 1.6
ref_plane "WorkPlane149" through (0, 0, 36.1) normal (0, 0, 1) x (1, 0, 0)
sketch "Button printable flange taper (7)" plane through (0, 0, 36.1) normal (0, 0, 1) x (1, 0, 0)
  circle A0 centre (-0.38, 5.86) radius 1.6
ref_plane "WorkPlane150" through (0, 0, 27.2) normal (0, 0, 1) x (1, 0, 0)
sketch "Keypad lower capture shelf" plane through (0, 0, 27.2) normal (0, 0, 1) x (1, 0, 0)
  line L0 (-13, -23.1) -> (-9, -23.1)
  line L1 (-9, -23.1) -> (-9, -21.3)
  line L2 (-9, -21.3) -> (-13, -21.3)
  line L3 (-13, -21.3) -> (-13, -23.1)
ref_plane "WorkPlane151" through (0, 0, 27.2) normal (0, 0, 1) x (1, 0, 0)
sketch "Keypad lower capture shelf (1)" plane through (0, 0, 27.2) normal (0, 0, 1) x (1, 0, 0)
  line L0 (-13, 9.3) -> (-9, 9.3)
  line L1 (-9, 9.3) -> (-9, 11.1)
  line L2 (-9, 11.1) -> (-13, 11.1)
  line L3 (-13, 11.1) -> (-13, 9.3)
ref_plane "WorkPlane152" through (0, 0, 27.2) normal (0, 0, 1) x (1, 0, 0)
sketch "Keypad lower capture shelf (2)" plane through (0, 0, 27.2) normal (0, 0, 1) x (1, 0, 0)
  line L0 (10, -23.1) -> (14, -23.1)
  line L1 (14, -23.1) -> (14, -21.3)
  line L2 (14, -21.3) -> (10, -21.3)
  line L3 (10, -21.3) -> (10, -23.1)
ref_plane "WorkPlane153" through (0, 0, 27.2) normal (0, 0, 1) x (1, 0, 0)
sketch "Keypad lower capture shelf (3)" plane through (0, 0, 27.2) normal (0, 0, 1) x (1, 0, 0)
  line L0 (10, 9.3) -> (14, 9.3)
  line L1 (14, 9.3) -> (14, 11.1)
  line L2 (14, 11.1) -> (10, 11.1)
  line L3 (10, 11.1) -> (10, 9.3)
ref_plane "WorkPlane154" through (0, 0, 30.2) normal (0, 0, 1) x (1, 0, 0)
sketch "OLED lower capture shelf" plane through (0, 0, 30.2) normal (0, 0, 1) x (1, 0, 0)
  line L0 (16.5, -24.35) -> (20.5, -24.35)
  line L1 (20.5, -24.35) -> (20.5, -22.55)
  line L2 (20.5, -22.55) -> (16.5, -22.55)
  line L3 (16.5, -22.55) -> (16.5, -24.35)
ref_plane "WorkPlane155" through (0, 0, 30.2) normal (0, 0, 1) x (1, 0, 0)
sketch "OLED lower capture shelf (1)" plane through (0, 0, 30.2) normal (0, 0, 1) x (1, 0, 0)
  line L0 (16.5, 11.55) -> (20.5, 11.55)
  line L1 (20.5, 11.55) -> (20.5, 13.35)
  line L2 (20.5, 13.35) -> (16.5, 13.35)
  line L3 (16.5, 13.35) -> (16.5, 11.55)
ref_plane "WorkPlane156" through (0, 0, 30.2) normal (0, 0, 1) x (1, 0, 0)
sketch "OLED lower capture shelf (2)" plane through (0, 0, 30.2) normal (0, 0, 1) x (1, 0, 0)
  line L0 (45.5, -24.35) -> (49.5, -24.35)
  line L1 (49.5, -24.35) -> (49.5, -22.55)
  line L2 (49.5, -22.55) -> (45.5, -22.55)
  line L3 (45.5, -22.55) -> (45.5, -24.35)
ref_plane "WorkPlane157" through (0, 0, 30.2) normal (0, 0, 1) x (1, 0, 0)
sketch "OLED lower capture shelf (3)" plane through (0, 0, 30.2) normal (0, 0, 1) x (1, 0, 0)
  line L0 (45.5, 11.55) -> (49.5, 11.55)
  line L1 (49.5, 11.55) -> (49.5, 13.35)
  line L2 (49.5, 13.35) -> (45.5, 13.35)
  line L3 (45.5, 13.35) -> (45.5, 11.55)
ref_plane "WorkPlane158" through (0, 0, 27.9) normal (0, 0, 1) x (1, 0, 0)
sketch "Keypad board seating clearance 0.1 mm" plane through (0, 0, 27.9) normal (0, 0, 1) x (1, 0, 0)
  line L0 (-14.15, -22.15) -> (15.15, -22.15)
  line L1 (15.15, -22.15) -> (15.15, 10.15)
  line L2 (15.15, 10.15) -> (-14.15, 10.15)
  line L3 (-14.15, 10.15) -> (-14.15, -22.15)
ref_plane "WorkPlane159" through (0, 0, 30.9) normal (0, 0, 1) x (1, 0, 0)
sketch "OLED board seating clearance 0.1 mm" plane through (0, 0, 30.9) normal (0, 0, 1) x (1, 0, 0)
  line L0 (16.1, -23.4) -> (49.9, -23.4)
  line L1 (49.9, -23.4) -> (49.9, 12.4)
  line L2 (49.9, 12.4) -> (16.1, 12.4)
  line L3 (16.1, 12.4) -> (16.1, -23.4)
ref_plane "WorkPlane160" through (51.9632, 0, 0) normal (1, 0, 0) x (0, 1, 0)